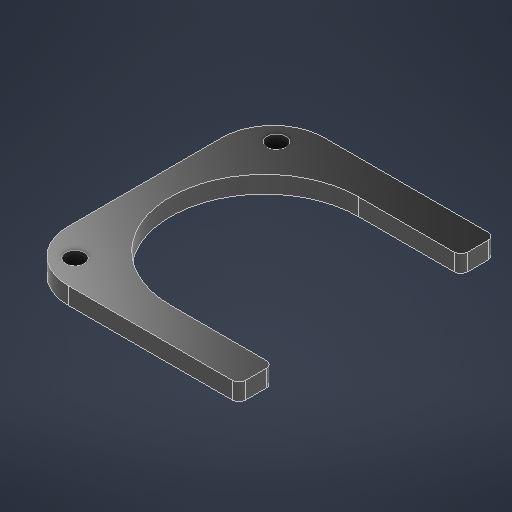
# Autodesk Inventor part: Magazine
Saved by Autodesk Inventor 2027.1 (Build 311270010, 270A)
## iProperties
Created: 2026-10-21
Part Number: Magazine
Material: MDF Medium Density Fiberboard
Document SubType Name: Modeling
Designer: SDS Scholar
Density: 0.8 g/cm^3
Appearance: Glossy - Black
Mass: 6.99124 g
Surface Area: 56.6812 cm^2
Volume: 8.73905 cm^3
Author: SDS Scholar
Autodesk Inventor part; units mm, degrees
ref_plane "YZ Plane" through (0, 0, 0) normal (1, 0, 0) x (0, 1, 0)
ref_plane "XZ Plane" through (0, 0, 0) normal (0, 1, 0) x (-1, 0, 0)
ref_plane "XY Plane" through (0, 0, 0) normal (0, 0, 1) x (1, 0, 0)
sketch "Sketch1" plane through (0, 0, 0) normal (0, 1, 0) x (-1, 0, 0)
  line L0 (-2.5, 27.5) -> (-32.5, 27.5)
  line L1 (-32.5, -27.5) -> (-2.5, -27.5)
  line L2 (32.5, 37.5) -> (-32.5, 37.5)
  line L3 (-32.5, 37.5) -> (-32.5, -37.5)
  line L4 (-32.5, -37.5) -> (32.5, -37.5)
  line L5 (32.5, -37.5) -> (32.5, 37.5)
  arc A0 (-2.5, -27.5) -> (-2.5, 27.5) centre (-2.5, 0) ccw
  point P0 (0, 0)
  point P1 (0, -27.5)
  point P2 (32.5, 0)
  point P3 (0, 37.5)
  point P4 (-32.5, -27.5)
  dimension "d1" = 55
  dimension "d10" = 65
  dimension "d11" = 75
  dimension "d15" = 27.5
  dimension "d32" = 30
  dimension "d33" = 30
  constraints: 12 end point, 3 parallel, 2 horizontal, 2 horizontal alignment, 2 midpoint, 2 point on circle, 2 point on line, 2 vertical alignment, 1 centre point, 1 perpendicular, 1 tangent
  measures "d1" distance of L0.end L1.start
  measures "d10" distance of L2.start L2.end
  measures "d11" distance of L4.end L2.start
  measures "d15" radius of A0
  measures "d32" distance of L1.start L1.end
  measures "d33" distance of L0.start L0.end
extrude "Extrusion1" add sketch "Sketch1" along normal blind 5 contours L0 L3 L2 L5 L4 L1 A0
fillet "Fillet1" radius 15 2 edges at (-32.5, 2.5, 37.5) (-32.5, 2.5, -37.5)
fillet "Fillet2" radius 2 4 edges at (32.5, 2.5, 37.5) (32.5, 2.5, 27.5) (32.5, 2.5, -27.5) (32.5, 2.5, -37.5)
sketch "Sketch2" plane through (0, 5, 0) normal (0, 1, 0) x (1, 0, 0)
  arc A0 (32.5, 35.5) -> (30.5, 37.5) centre (30.5, 35.5) ccw projected
  line L0 (30.5, 37.5) -> (-17.5, 37.5) projected
  arc A1 (-17.5, 37.5) -> (-32.5, 22.5) centre (-17.5, 22.5) ccw projected
  line L1 (-32.5, 22.5) -> (-32.5, -22.5) projected
  arc A2 (-32.5, -22.5) -> (-17.5, -37.5) centre (-17.5, -22.5) ccw projected
  line L2 (-17.5, -37.5) -> (30.5, -37.5) projected
  arc A3 (30.5, -37.5) -> (32.5, -35.5) centre (30.5, -35.5) ccw projected
  line L3 (32.5, -35.5) -> (32.5, -29.5) projected
  arc A4 (32.5, -29.5) -> (30.5, -27.5) centre (30.5, -29.5) ccw projected
  line L4 (30.5, -27.5) -> (2.5, -27.5) projected
  arc A5 (2.5, 27.5) -> (2.5, -27.5) centre (2.5, 0) ccw projected
  line L5 (2.5, 27.5) -> (30.5, 27.5) projected
  arc A6 (30.5, 27.5) -> (32.5, 29.5) centre (30.5, 29.5) ccw projected
  line L6 (32.5, 29.5) -> (32.5, 35.5) projected
  circle A7 centre (-23.5, -29.5) radius 2.5
  line L7 (-32.5, 0) -> (0, 0) construction
  circle A8 centre (-23.5, 29.5) radius 2.5
  dimension "d20" = 5
  dimension "d21" = 8
  dimension "d22" = 9
  constraints: 2 centre point, 2 end point, 1 horizontal, 1 midpoint, 1 symmetric about line, 1 other
  measures "d20" diameter of A7
  measures "d21" distance from line of L2 A7.centre
  measures "d22" distance from line of L1 A7.centre
hole "Hole1" at (-23.5, 5, -29.5) at (-23.5, 5, 29.5) direction (0, -1, 0) diameter 5.5 end through all clearance for "Countersunk Flat Head Screw ISO 2009/7046" size "M5" standard "ISO"
equation "\"GridProcutClearance\" = 5"
equation "\"GridBorderThickness\" = 5"
equation "\"GridBorderFillets\" = 7"
equation "\"GridTotalSize\" = 65"
equation "\"GridRobotClearance\" = 65"
equation "\"AluminiumExtrusionClearance\" = 35"
equation "\"BaseTotalLength\" = 885"
equation "\"WorkspaceLength\" = 515"
equation "\"WorkspaceHeight\" = 183"
equation "\"AxesBaseFillet\" = 15"
equation "\"Zaxis\" = 197"
equation "\"ProductTotalHeight\" = 45"
equation "\"VerticalStroke\" = 105"
equation "\"BackArea\" = 165"
equation "\"CylinderStroke\" = 75"
equation "\"BoxesWidth\" = 125"
equation "\"BaseWoodThickness\" = 7"
equation "\"Kerf\" = 0.3"
equation "\"RxThickness\" = 1.8"
equation "\"support_2\" = 265"
body "Solid1"
